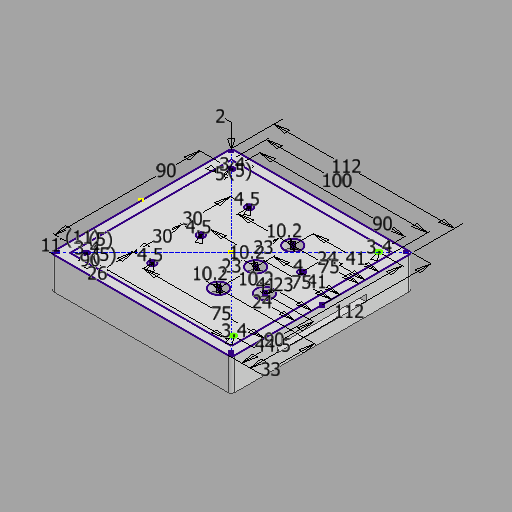
# Autodesk Inventor part: SENSOR_Top
Saved by Autodesk Inventor 2027 (Build 310192000, 192)
## iProperties
Created: 2026-11-12
Part Number: SENSOR_Top
Material: Generic
Document SubType Name: Modeling
Designer: jyjhm
Density: 1 g/cm^3
Appearance: Default
Author: jyjhm
Autodesk Inventor part; units mm, degrees
ref_plane "YZ Plane" through (0, 0, 0) normal (1, 0, 0) x (0, 1, 0)
ref_plane "XZ Plane" through (0, 0, 0) normal (0, 1, 0) x (-1, 0, 0)
ref_plane "XY Plane" through (0, 0, 0) normal (0, 0, 1) x (1, 0, 0)
sketch "Sketch1" plane through (0, 0, 0) normal (0, 1, 0) x (-1, 0, 0)
  line L0 (-54, -56) -> (54, -56)
  line L1 (56, -54) -> (56, 54)
  line L2 (54, 56) -> (-54, 56)
  line L3 (-56, 54) -> (-56, -54)
  line L4 (-56, -56) -> (56, 56) construction
  line L5 (56, -56) -> (-56, 56) construction
  line L6 (-50, -50) -> (50, -50)
  line L7 (50, -50) -> (50, 50)
  line L8 (50, 50) -> (-50, 50)
  line L9 (-50, 50) -> (-50, -50)
  line L10 (-50, -50) -> (50, 50) construction
  line L11 (50, -50) -> (-50, 50) construction
  arc A0 (54, -56) -> (56, -54) centre (54, -54) ccw
  arc A1 (-56, -54) -> (-54, -56) centre (-54, -54) ccw
  arc A2 (-54, 56) -> (-56, 54) centre (-54, 54) ccw
  arc A3 (56, 54) -> (54, 56) centre (54, 54) ccw
  circle A4 centre (19, 30) radius 2.25
  circle A5 centre (-15, 23) radius 5.1
  circle A6 centre (19, 0) radius 2.25
  circle A7 centre (19, -30) radius 2.25
  circle A8 centre (-15, 0) radius 5.1
  circle A9 centre (-15, -23) radius 5.1
  circle A10 centre (-32, 11.5) radius 5.1
  circle A11 centre (-32, -11.5) radius 2
  circle A12 centre (45, 45) radius 1.7
  circle A13 centre (-45, 43.8997) radius 1.7
  circle A14 centre (45, -45) radius 1.7
  circle A15 centre (-45, -46.1003) radius 1.7
  point P0 (0, 0)
  point P1 (-56, 0)
  dimension "d0" = 112
  dimension "d1" = 112
  dimension "d2" = 100
  dimension "d3" = 2
  dimension "d4" = 4.5
  dimension "d5" = 75
  dimension "d6" = 26
  dimension "d7" = 4.5
  dimension "d8" = 4.5
  dimension "d9" = 75
  dimension "d10" = 75
  dimension "d11" = 30
  dimension "d12" = 30
  dimension "d13" = 41
  dimension "d14" = 33
  dimension "d15" = 10.2
  dimension "d16" = 10.2
  dimension "d17" = 10.2
  dimension "d18" = 10.2
  dimension "d19" = 4
  dimension "d20" = 41
  dimension "d21" = 41
  dimension "d22" = 24
  dimension "d23" = 24
  dimension "d24" = 23
  dimension "d25" = 23
  dimension "d26" = 44.5
  dimension "d27" = 23
  dimension "d28" = 3.4
  dimension "d29" = 3.4
  dimension "d30" = 3.4
  dimension "d31" = 3.4
  dimension "d32" = 90
  dimension "d33" = 90
  dimension "d34" = 90
  dimension "d35" = 90
  dimension "d36" = 11
  dimension "d37" = 11
  dimension "d67" = 5
  dimension "d68" = 5
  dimension "d69" = 5
  dimension "d70" = 5
  constraints: 24 end point, 16 centre point, 10 point on line, 8 point on circle, 8 tangent, 5 midpoint, 4 parallel, 3 equal radius, 2 horizontal, 2 perpendicular
  measures "d0" distance of L5.end L4.start
  measures "d1" distance of L4.start L5.start
  measures "d2" distance of L6.start L6.end
  measures "d3" radius of A0
  measures "d4" diameter of A4
  measures "d5" distance from line of L3 A4.centre
  measures "d6" distance from line of L2 A4.centre
  measures "d7" diameter of A6
  measures "d8" diameter of A7
  measures "d9" distance from line of L3 A6.centre
  measures "d10" distance from line of L3 A7.centre
  measures "d11" distance of A6.centre A4.centre
  measures "d12" distance of A6.centre A7.centre
  measures "d13" distance from line of L3 A5.centre
  measures "d14" distance from line of L2 A5.centre
  measures "d15" diameter of A5
  measures "d16" diameter of A8
  measures "d17" diameter of A9
  measures "d18" diameter of A10
  measures "d19" diameter of A11
  measures "d20" distance of point (-56, 0) A8.centre
  measures "d21" distance from line of L3 A9.centre
  measures "d22" distance from line of A10.centre L3
  measures "d23" distance from line of A11.centre L3
  measures "d24" distance of A8.centre A5.centre
  measures "d25" distance of A9.centre A8.centre
  measures "d26" distance from line of L2 A10.centre
  measures "d27" distance of A11.centre A10.centre
  measures "d28" diameter of A12
  measures "d29" diameter of A13
  measures "d30" diameter of A14
  measures "d31" diameter of A15
  measures "d32" distance of A14.centre A12.centre
  measures "d33" horizontal distance of A15.centre A14.centre
  measures "d34" distance of A13.centre A15.centre
  measures "d35" horizontal distance of A12.centre A13.centre
  measures "d36" distance from line of L2 A12.centre
  measures "d37" distance from line of L1 A12.centre
  measures "d67" distance from line of L7 A14.centre
  measures "d68" distance from line of L7 A12.centre
  measures "d69" distance from line of L8 A12.centre
  measures "d70" distance from line of L6 A14.centre
extrude "Extrusion1" add sketch "Sketch1" against normal blind 5 contours L9 L8 L7 L6
extrude "Extrusion3" add sketch "Sketch1" against normal blind 20 contours A1 L3 A2 L2 A3 L1 A0 L0
sketch "Sketch2" plane through (56, 0, 54) normal (1, 0, 0) x (0, 0, -1)
  line L0 (81.5, -12) -> (26.5, -12)
  line L1 (26.5, -12) -> (26.5, -8)
  line L2 (26.5, -8) -> (81.5, -8)
  line L3 (81.5, -8) -> (81.5, -12)
  line L4 (81.5, -12) -> (26.5, -8) construction
  line L5 (26.5, -12) -> (81.5, -8) construction
  line L6 (0, 0) -> (0, -20) projected
  line L7 (108, 0) -> (108, -20) projected
  line L8 (108, -20) -> (0, -20) projected
  line L9 (84, -14.5) -> (24, -14.5)
  line L10 (24, -14.5) -> (24, -5.5)
  line L11 (24, -5.5) -> (84, -5.5)
  line L12 (84, -5.5) -> (84, -14.5)
  line L13 (84, -14.5) -> (24, -5.5) construction
  line L14 (24, -14.5) -> (84, -5.5) construction
  line L15 (104, -5) -> (4, -5) projected
  line L16 (104, -5) -> (104, -20) projected
  line L17 (4, -20) -> (104, -20) projected
  line L18 (4, -5) -> (4, -20) projected
  point P0 (54, 0)
  point P1 (54, -10)
  point P2 (0, -10)
  dimension "d44" = 4
  dimension "d45" = 55
  dimension "d46" = 54
  dimension "d47" = 108
  dimension "d48" = 20
  dimension "d49" = 10
  dimension "d52" = 9
  dimension "d53" = 60
  dimension "d71" = 5.5
  constraints: 24 end point, 5 midpoint, 4 parallel, 2 horizontal, 2 perpendicular
  measures "d44" distance of L2.end L0.start
  measures "d45" distance of L0.start L0.end
  measures "d46" distance of point (0, -10) point (54, -10)
  measures "d47" distance between parallel lines of L7 L6
  measures "d48" distance of L7.start L7.end
  measures "d49" distance from line of L8 point (54, -10)
  measures "d52" distance of L11.end L9.start
  measures "d53" distance of L10.end L11.end
  measures "d71" distance between parallel lines of L8 L9
extrude "Extrusion4" cut sketch "Sketch2" against normal blind 6 contours L0 L1 L2 L3
sketch "Sketch4" plane through (50, -20, -50) normal (-1, 0, 0) x (0, 0, 1)
  line L0 (80, 5.5) -> (20, 5.5)
  line L1 (20, 5.5) -> (20, 14.5)
  line L2 (20, 14.5) -> (80, 14.5)
  line L3 (80, 14.5) -> (80, 5.5)
  line L4 (80, 5.5) -> (20, 14.5) construction
  line L5 (20, 5.5) -> (80, 14.5) construction
  line L6 (77.5, 8) -> (22.5, 8) projected
  line L7 (22.5, 12) -> (77.5, 12) projected
  line L8 (22.5, 8) -> (22.5, 12) projected
  line L9 (77.5, 12) -> (77.5, 8) projected
  line L10 (100, 0) -> (0, 0) projected
  line L11 (0, 15) -> (0, 0) projected
  line L12 (0, 15) -> (100, 15) projected
  line L13 (100, 15) -> (100, 0) projected
  line L14 (80.5, 5) -> (19.5, 5)
  line L15 (19.5, 5) -> (19.5, 15)
  line L16 (19.5, 15) -> (80.5, 15)
  line L17 (80.5, 15) -> (80.5, 5)
  line L18 (80.5, 5) -> (19.5, 15) construction
  line L19 (19.5, 5) -> (80.5, 15) construction
  point P0 (50, 20)
  point P1 (50, 10)
  dimension "d54" = 2.5
  dimension "d55" = 2.5
  dimension "d56" = 2.5
  dimension "d57" = 2.5
  dimension "d58" = 0.5
  dimension "d59" = 0.5
  dimension "d60" = 0.5
  constraints: 24 end point, 4 midpoint, 4 parallel, 2 horizontal, 2 perpendicular, 1 point on line
  measures "d54" distance between parallel lines of L0 L6
  measures "d55" distance between parallel lines of L2 L7
  measures "d56" distance between parallel lines of L3 L9
  measures "d57" distance between parallel lines of L1 L8
  measures "d58" distance between parallel lines of L2 L16
  measures "d59" distance between parallel lines of L14 L0
  measures "d60" distance between parallel lines of L15 L1
extrude "Extrusion5" add sketch "Sketch4" along normal blind 5 contours L17 L14 L15 L12
sketch "Sketch5" plane through (-56, 0, -54) normal (-1, 0, 0) x (0, 0, 1)
  line L0 (84.5, -15) -> (84.5, -5) projected
  line L1 (23.5, -5) -> (84.5, -5) projected
  line L2 (23.5, -5) -> (23.5, -15) projected
  line L3 (23.5, -15) -> (84.5, -15) projected
  line L4 (84, -14.5) -> (24, -14.5) projected
  line L5 (24, -14.5) -> (24, -5.5) projected
  line L6 (24, -5.5) -> (84, -5.5) projected
  line L7 (84, -5.5) -> (84, -14.5) projected
  line L8 (26.5, -8) -> (81.5, -8) projected
  line L9 (26.5, -12) -> (26.5, -8) projected
  line L10 (81.5, -12) -> (26.5, -12) projected
  line L11 (81.5, -8) -> (81.5, -12) projected
  point P0 (54, 0)
extrude "Extrusion6" cut sketch "Sketch5" against normal blind 6 contours L8 L11 L10 L9
sketch "Sketch6" plane through (-50, -20, 50) normal (1, 0, 0) x (0, 0, -1)
  line L0 (80.5, 15) -> (80.5, 5) projected
  line L1 (80, 5.5) -> (80, 14.5) projected
  line L2 (80, 14.5) -> (20, 14.5) projected
  line L3 (80.5, 15) -> (19.5, 15) projected
  line L4 (20, 5.5) -> (80, 5.5) projected
  line L5 (80.5, 5) -> (19.5, 5) projected
  line L6 (20, 14.5) -> (20, 5.5) projected
  line L7 (19.5, 5) -> (19.5, 15) projected
  point P0 (50, 20)
extrude "Extrusion7" add sketch "Sketch6" along normal blind 5
body "Solid1"
